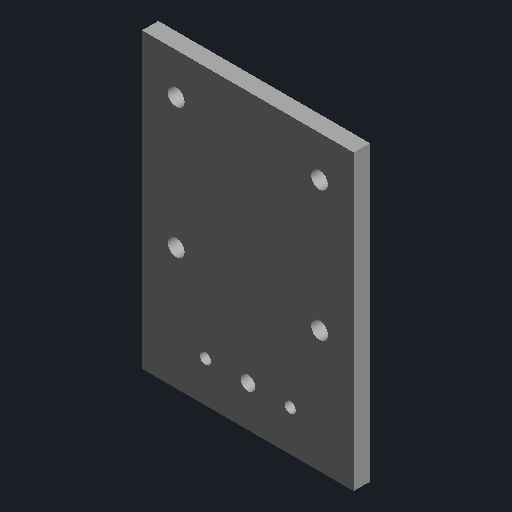
# Autodesk Inventor part: Carro_Transversal_Gantry
Saved by Autodesk Inventor 2027.2 (Build 312334000, 334)
## iProperties
Part Number: Carro_Transversal_Gantry
Material: Genérico
Document SubType Name: Modelado
Designer: Usuario
Appearance: Por defecto
Author: Usuario
Autodesk Inventor part; units mm, degrees
ref_plane "Plano YZ" through (0, 0, 0) normal (1, 0, 0) x (0, 1, 0)
ref_plane "Plano XZ" through (0, 0, 0) normal (0, 1, 0) x (-1, 0, 0)
ref_plane "Plano XY" through (0, 0, 0) normal (0, 0, 1) x (1, 0, 0)
sketch "Boceto1" plane through (0, 0, 0) normal (0, 0, 1) x (1, 0, 0)
  line L0 (-32.5, -32.5) -> (32.5, -32.5)
  line L1 (32.5, -32.5) -> (32.5, 32.5)
  line L2 (32.5, 32.5) -> (-32.5, 32.5)
  line L3 (-32.5, 32.5) -> (-32.5, -32.5)
  line L4 (-32.5, -57.5) -> (32.5, -57.5)
  line L5 (32.5, -57.5) -> (32.5, -32.5)
  line L6 (32.5, -32.5) -> (-32.5, -32.5)
  line L7 (-32.5, -32.5) -> (-32.5, -57.5)
  circle A0 centre (-22, 20) radius 2.6
  circle A1 centre (22, 20) radius 2.6
  circle A2 centre (-22, -20) radius 2.6
  circle A3 centre (22, -20) radius 2.6
  circle A4 centre (0, -45) radius 2.25
  circle A5 centre (-13, -45) radius 1.7
  circle A6 centre (13, -45) radius 1.7
  constraints: 16 end point, 7 centre point, 4 parallel, 2 horizontal, 2 perpendicular
extrude "Extrusión1" add sketch "Boceto1" along normal blind 5
